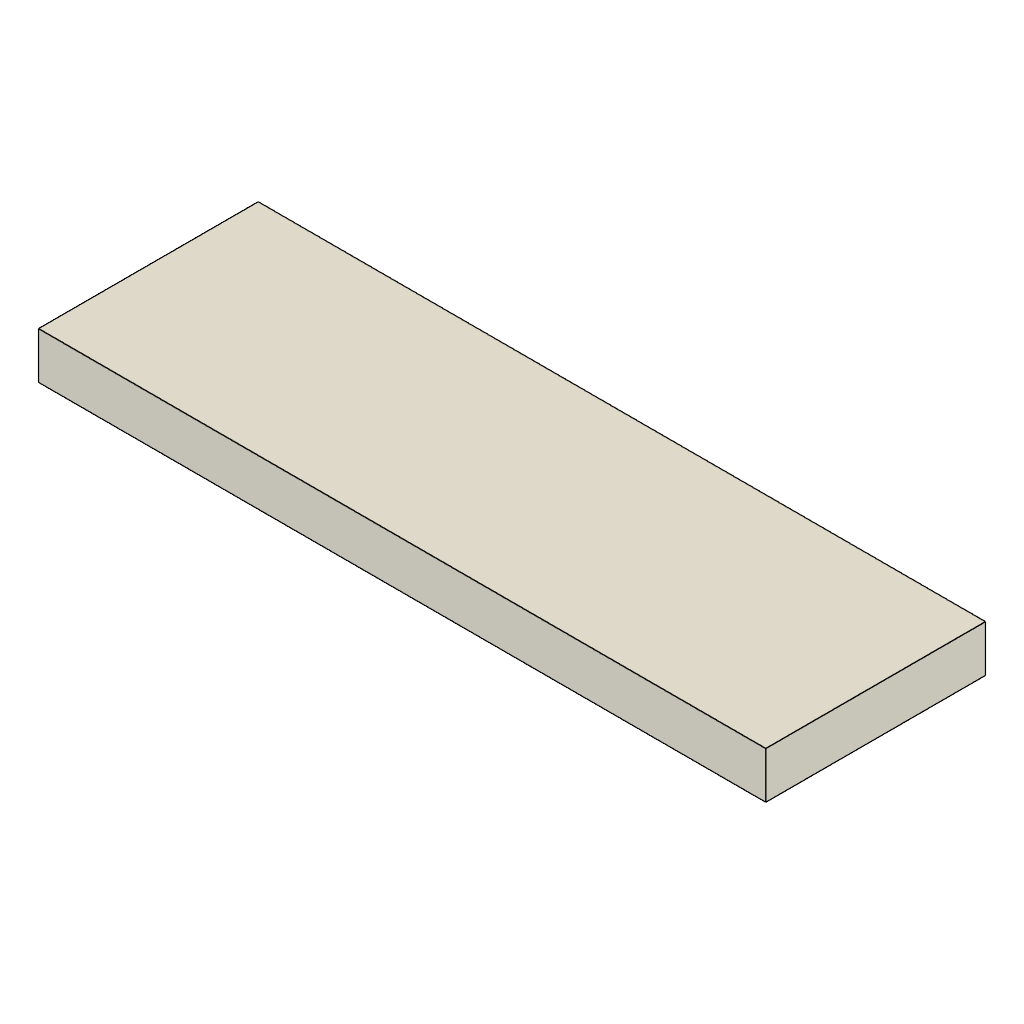
Keycap (3u Space Right) (Autodesk Fusion 360 archive; units mm, degrees)
design "Keycap (3u Space base)" references "_Globals"
part number: 2026-10-16-15-32-49-082
Autodesk Fusion 360 part; units mm, degrees
derive "Derived from _Globals"
sketch "Sketch1" plane through (0, 0, 0) normal (0, 1, 0) x (1, 0, 0)
  line L0 (-27.3, -8.25) -> (27.3, -8.25)
  line L1 (27.3, -8.25) -> (27.3, 8.25)
  line L2 (27.3, 8.25) -> (-27.3, 8.25)
  line L3 (-27.3, 8.25) -> (-27.3, -8.25)
  line L4 (-27.3, -8.25) -> (27.3, 8.25) construction
  line L5 (27.3, -8.25) -> (-27.3, 8.25) construction
  dimension "d14" = 54.6
  dimension "d15" = 16.5
  constraint horizontal L0
  constraint perpendicular L0 L1
  constraint parallel L0 L2
  constraint parallel L1 L3
  constraint coincident L4 origin
  constraint coincident L5 origin
  measures "d14" distance of L1.end L2.end
  measures "d15" distance of L0.end L1.end
extrude "Extrude1" add sketch "Sketch1" along normal blind 3.5
sketch "Sketch2" plane through (0, 0, 0) normal (0, -1, 0) x (1, 0, 0)
  line L0 (-27.3, -8.25) -> (27.3, -8.25)
  line L1 (27.3, -8.25) -> (27.3, 8.25)
  line L2 (27.3, 8.25) -> (-27.3, 8.25)
  line L3 (-27.3, 8.25) -> (-27.3, -8.25)
  line L4 (26.3, 7.25) -> (-26.3, 7.25)
  line L5 (-26.3, 7.25) -> (-26.3, -7.25)
  line L6 (-26.3, -7.25) -> (26.3, -7.25)
  line L7 (26.3, -7.25) -> (26.3, 7.25)
extrude "Extrude2" cut sketch "Sketch2" against normal blind 2.05 contours L4 L5 L6 L7
sketch "Sketch3" plane through (0, 2.05, 0) normal (0, -1, 0) x (1, 0, 0)
  line L0 (26.3, -7.25) -> (26.3, 7.25)
  line L1 (26.3, 7.25) -> (-26.3, 7.25)
  line L2 (-26.3, 7.25) -> (-26.3, -7.25)
  line L3 (-26.3, -7.25) -> (26.3, -7.25)
  line L4 (0, 0) -> (-18, 0) construction
  line L5 (-18, 0) -> (-18, 2.05) construction
  line L6 (-18.7, 2.05) -> (-17.3, 2.05)
  line L7 (-17.3, 2.05) -> (-17.3, 0.7)
  line L8 (-17.3, 0.7) -> (-15.95, 0.7)
  line L9 (-20.05, -0.7) -> (-20.05, 0.7)
  line L10 (-20.05, 0.7) -> (-18.7, 0.7)
  line L11 (-18.7, 0.7) -> (-18.7, 2.05)
  line L12 (-17.3, -2.05) -> (-18.7, -2.05)
  line L13 (-18.7, -2.05) -> (-18.7, -0.7)
  line L14 (-18.7, -0.7) -> (-20.05, -0.7)
  line L15 (-15.95, 0.7) -> (-15.95, -0.7)
  line L16 (-15.95, -0.7) -> (-17.3, -0.7)
  line L17 (-17.3, -0.7) -> (-17.3, -2.05)
  line L18 (-20.7, -1.35) -> (-20.7, 1.35)
  line L19 (-20.7, 1.35) -> (-19.35, 1.35)
  line L20 (-19.35, 1.35) -> (-19.35, 2.7)
  line L21 (-19.35, 2.7) -> (-16.65, 2.7)
  line L22 (-16.65, 2.7) -> (-16.65, 1.35)
  line L23 (-16.65, 1.35) -> (-15.3, 1.35)
  line L24 (-15.3, 1.35) -> (-15.3, -1.35)
  line L25 (-15.3, -1.35) -> (-16.65, -1.35)
  line L26 (-16.65, -1.35) -> (-16.65, -2.7)
  line L27 (-16.65, -2.7) -> (-19.35, -2.7)
  line L28 (-19.35, -2.7) -> (-19.35, -1.35)
  line L29 (-19.35, -1.35) -> (-20.7, -1.35)
  line L30 (0, 0) -> (0, 2.05) construction
  line L31 (0, 2.05) -> (-0.7, 2.05)
  line L32 (-0.7, 2.05) -> (-0.7, 0.7)
  line L33 (-0.7, 0.7) -> (-2.05, 0.7)
  line L34 (-2.05, 0.7) -> (-2.05, 0)
  line L35 (0, -2.05) -> (-0.7, -2.05)
  line L36 (-0.7, -2.05) -> (-0.7, -0.7)
  line L37 (-0.7, -0.7) -> (-2.05, -0.7)
  line L38 (-2.05, -0.7) -> (-2.05, 0)
  line L39 (16.65, 1.35) -> (15.3, 1.35)
  line L40 (15.3, 1.35) -> (15.3, -1.35)
  line L41 (15.3, -1.35) -> (16.65, -1.35)
  line L42 (16.65, -1.35) -> (16.65, -2.7)
  line L43 (16.65, -2.7) -> (19.35, -2.7)
  line L44 (19.35, -2.7) -> (19.35, -1.35)
  line L45 (19.35, -1.35) -> (20.7, -1.35)
  line L46 (20.7, -1.35) -> (20.7, 1.35)
  line L47 (20.7, 1.35) -> (19.35, 1.35)
  line L48 (19.35, 1.35) -> (19.35, 2.7)
  line L49 (16.65, 2.7) -> (16.65, 1.35)
  line L50 (19.35, 2.7) -> (16.65, 2.7)
  line L51 (18.7, 2.05) -> (17.3, 2.05)
  line L52 (17.3, 0.7) -> (15.95, 0.7)
  line L53 (17.3, 2.05) -> (17.3, 0.7)
  line L54 (15.95, 0.7) -> (15.95, -0.7)
  line L55 (17.3, -0.7) -> (17.3, -2.05)
  line L56 (15.95, -0.7) -> (17.3, -0.7)
  line L57 (17.3, -2.05) -> (18.7, -2.05)
  line L58 (18.7, -0.7) -> (20.05, -0.7)
  line L59 (18.7, -2.05) -> (18.7, -0.7)
  line L60 (20.05, -0.7) -> (20.05, 0.7)
  line L61 (20.05, 0.7) -> (18.7, 0.7)
  line L62 (18.7, 0.7) -> (18.7, 2.05)
  line L63 (0, 2.05) -> (0.7, 2.05)
  line L64 (0.7, 0.7) -> (2.05, 0.7)
  line L65 (2.05, 0.7) -> (2.05, 0)
  line L66 (0.7, 2.05) -> (0.7, 0.7)
  line L67 (0, -2.05) -> (0.7, -2.05)
  line L68 (0.7, -2.05) -> (0.7, -0.7)
  line L69 (2.05, -0.7) -> (2.05, 0)
  line L70 (0.7, -0.7) -> (2.05, -0.7)
  circle A0 centre (0, 0) radius 2.7
  dimension "d26" = 18
  dimension "d27" = 2.05
  dimension "d28" = 1.4
  dimension "d29" = 1.35
  dimension "d30" = 1.35
  dimension "d32" = 360
  dimension "d33" = -0.65
  dimension "d34" = 2.05
  dimension "d35" = 0.7
  dimension "d36" = 1.35
  dimension "d37" = 1.35
  dimension "d38" = 5.4
  constraint coincident L4.start L30.start
  constraint horizontal L4
  constraint perpendicular L4 L5
  constraint horizontal L6
  constraint midpoint L5.end L6
  constraint perpendicular L6 L7
  constraint perpendicular L7 L8
  constraint perpendicular L4 L30
  constraint perpendicular L30 L31
  constraint perpendicular L31 L32
  constraint perpendicular L32 L33
  constraint coincident L4 L34.end
  constraint perpendicular L4 L34
  constraint symmetric L4 L30.end L35.start
  constraint symmetric L4 L31.end L35.end
  constraint symmetric L4 L32.end L36.end
  constraint symmetric L4 L33.end L37.end
  constraint symmetric L4 L34.end L38.end
  constraint symmetric L6.start L30 L51.start
  constraint symmetric L6.end L30 L51.end
  constraint symmetric L7.end L30 L52.start
  constraint symmetric L8.end L30 L52.end
  constraint symmetric L9.start L30 L58.end
  constraint symmetric L9.end L30 L60.end
  constraint symmetric L10.end L30 L61.end
  constraint symmetric L12.start L30 L55.end
  constraint symmetric L12.end L30 L57.end
  constraint symmetric L13.end L30 L58.start
  constraint symmetric L15.end L30 L54.end
  constraint symmetric L16.end L30 L55.start
  constraint symmetric L18.start L30 L45.end
  constraint symmetric L18.end L30 L46.end
  constraint symmetric L19.end L30 L47.end
  constraint symmetric L20.end L30 L48.end
  constraint symmetric L21.end L30 L49.start
  constraint symmetric L22.end L30 L39.start
  constraint symmetric L23.end L30 L39.end
  constraint symmetric L24.end L30 L40.end
  constraint symmetric L25.end L30 L41.end
  constraint symmetric L26.end L30 L42.end
  constraint symmetric L27.end L30 L43.end
  constraint symmetric L28.end L30 L44.end
  constraint symmetric L31.start L30 L63.start
  constraint symmetric L30 L31.end L63.end
  constraint symmetric L30 L32.end L64.start
  constraint symmetric L30 L33.end L64.end
  constraint symmetric L30 L34.end L65.end
  constraint symmetric L30 L35.start L67.start
  constraint symmetric L30 L35.end L67.end
  constraint symmetric L30 L36.end L68.end
  constraint symmetric L30 L37.end L69.start
  measures "d26" distance of L4.start L4.end
  measures "d27" distance of L4.end L5.end
  measures "d28" distance of L6.start L6.end
  measures "d29" distance of L6.end L7.end
  measures "d30" distance of L7.end L8.end
  measures "d34" distance of L4.start L30.end
  measures "d35" distance of L30.end L31.end
  measures "d36" distance of L31.end L32.end
  measures "d37" distance of L32.end L33.end
  measures "d38" diameter of A0
extrude "Extrude3" add sketch "Sketch3" along normal blind 3.35 contours L18 L19 L20 L21 L22 L23 L24 L25 L26 L27 L28 L29 | L39 L40 L41 L42 L43 L44 L45 L46 L47 L48 L49 L50 | A0
fillet "Fillet3" radius 0.1 5 edges at (-2.5173, -1.3, -0.9764) (0.7, 0.375, -0.7) (-0.7, 0.375, -0.7) (0.7, 0.375, 0.7) (-0.7, 0.375, 0.7)
fillet "Fillet4" radius 0.1 28 edges at (19.35, 0.375, -2.7) (19.35, 0.375, -1.35) (20.7, 0.375, -1.35) (20.7, 0.375, 1.35) (19.35, 0.375, 1.35) (19.35, 0.375, 2.7) (16.65, 0.375, 2.7) (16.65, 0.375, 1.35) (15.3, 0.375, 1.35) (15.3, 0.375, -1.35) (16.65, 0.375, -1.35) (16.65, 0.375, -2.7) (16.65, -1.3, -2.025) (18, -1.3, -2.7) (15.975, -1.3, -1.35) (15.3, -1.3, 0) (15.975, -1.3, 1.35) (16.65, -1.3, 2.025) (18, -1.3, 2.7) (19.35, -1.3, 2.025) (20.025, -1.3, 1.35) (20.7, -1.3, 0) (20.025, -1.3, -1.35) (19.35, -1.3, -2.025) (18.7, 0.375, -0.7) (18.7, 0.375, 0.7) (17.3, 0.375, 0.7) (17.3, 0.375, -0.7)
fillet "Fillet5" radius 0.1 28 edges at (-16.65, 0.375, 2.7) (-19.35, 0.375, 2.7) (-20.7, 0.375, 1.35) (-15.3, 0.375, 1.35) (-15.975, -1.3, 1.35) (-16.65, -1.3, 2.025) (-18, -1.3, 2.7) (-19.35, -1.3, 2.025) (-20.025, -1.3, 1.35) (-16.65, 0.375, 1.35) (-19.35, 0.375, 1.35) (-20.7, -1.3, 0) (-20.7, 0.375, -1.35) (-19.35, 0.375, -1.35) (-20.025, -1.3, -1.35) (-19.35, -1.3, -2.025) (-19.35, 0.375, -2.7) (-18, -1.3, -2.7) (-16.65, 0.375, -2.7) (-16.65, -1.3, -2.025) (-16.65, 0.375, -1.35) (-15.975, -1.3, -1.35) (-15.3, 0.375, -1.35) (-15.3, -1.3, 0) (-17.3, 0.375, -0.7) (-18.7, 0.375, -0.7) (-17.3, 0.375, 0.7) (-18.7, 0.375, 0.7)
fillet "Fillet6" radius 0.5 4 edges at (26.3, 1.025, -7.25) (26.3, 1.025, 7.25) (-26.3, 1.025, 7.25) (-26.3, 1.025, -7.25)
equation "keycap_size_Ref = 16.5 mm"
equation "keycap_thickness_Ref = 3.5 mm" comment "Keycap thickness without stem"
equation "keycap_full_thickness_Ref = 4.8 mm" comment "Keycap thickness from stem to top"
equation "keycap_top_fillet_Ref = 0.5 mm"
equation "keycap_side_fillet_Ref = 1 mm"
equation "stem_fillet_Ref = 0.1 mm"
equation "stem_diameter_Ref = 5.5 mm"
equation "stem_cross_length_Ref = 4 mm"
equation "stem_cross_width_Ref = 1.3 mm"
equation "stem_offset_Ref = 0.1 mm"
equation "keycap_side_width_Ref = 1 mm"
equation "keycap_inner_thickness_Ref = keycap_full_thickness_Ref - 3.35 mm"
equation "switch_size_Ref = 19.05 mm"
equation "d14 = keycap_size_Ref + switch_size_Ref * 2"
equation "d15 = keycap_size_Ref"
equation "d16 = keycap_thickness_Ref"
equation "d22 = -keycap_side_width_Ref"
equation "d23 = -( keycap_thickness_Ref - keycap_inner_thickness_Ref )"
equation "stabilizer_distance = 18 mm"
equation "d26 = stabilizer_distance"
equation "d27 = ( stem_cross_length_Ref + stem_offset_Ref ) * 0.5"
equation "d28 = stem_cross_width_Ref + stem_offset_Ref"
equation "d29 = ( stem_cross_length_Ref - stem_cross_width_Ref ) * 0.5"
equation "d30 = ( stem_cross_length_Ref - stem_cross_width_Ref ) * 0.5"
equation "d33 = -( ( stem_diameter_Ref - stem_offset_Ref - ( stem_cross_length_Ref + stem_offset_Ref ) ) * 0.5 )"
equation "d34 = ( stem_cross_length_Ref + stem_offset_Ref ) * 0.5"
equation "d35 = ( stem_cross_width_Ref + stem_offset_Ref ) * 0.5"
equation "d36 = ( stem_cross_length_Ref - stem_cross_width_Ref ) * 0.5"
equation "d37 = ( stem_cross_length_Ref - stem_cross_width_Ref ) * 0.5"
equation "d38 = stem_diameter_Ref - stem_offset_Ref"
equation "d39 = keycap_full_thickness_Ref - keycap_inner_thickness_Ref"
equation "d42 = stem_fillet_Ref"
equation "d44 = stem_fillet_Ref"
equation "d46 = stem_fillet_Ref"
equation "d48 = keycap_side_fillet_Ref * 0.5"
named bodies: "Main"
